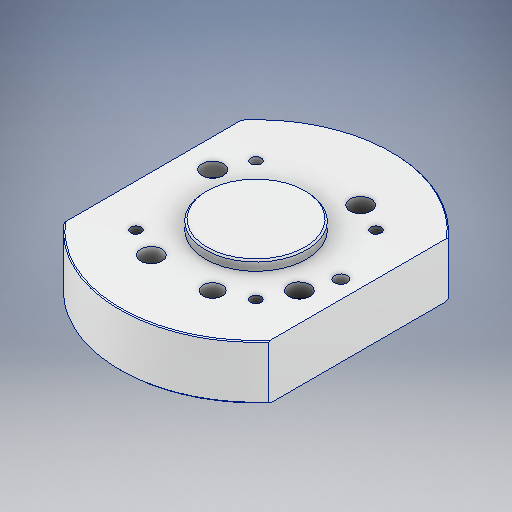
# Autodesk Inventor part: SCHUNK-0302201 A-SWK-020-ISO-A50
Saved by Autodesk Inventor 2025.3 (Build 293356000, 356)
## iProperties
Category: PARTsolutions
Company: SCHUNK
Created: 2026-08-11
Part Number: SCHUNK-0302201 A-SWK-020-ISO-A50
Material: Aluminium 6061
Catalog Web Link: www.3dfindit.com
Description: Adapter plate-Adapter plate
Vendor: SCHUNK
Document SubType Name: Modeling
Designer: psAdmin
Manufacturer: SCHUNK
Mass: 174.754 g
Surface Area: 171.893 cm^2
Volume: 64.7236 cm^3
Density: 2.7 g/cm^3
Appearance: Aluminium - flach
PSOL_IDENT_0: {$CADENAS_DATA/23d-libs/schunk/greifsysteme/roboterzubehoer/wechseln/optionen_fuer_sws/adapterplatte
PSOL_IDENT_1: n/adapterplatten.prj},212 {VTYP=3D},{NB=SCHUNK-0302201 A-SWK-020-ISO-A50},{LINA=SCHUNK-0302201 A-SWK
PSOL_IDENT_2: -020-ISO-A50},{NN=Adapter plate},{DATE=18.09.2025 11:03:46},{GEOMDATE=15.03.2023 10:20:12},{VERSION=
PSOL_IDENT_3: },{LINEID=610},{WBVAR=},{WBNUMERIC=}  {NB=SCHUNK-0302201 A-SWK-020-ISO-A50},{LINA=SCHUNK-0302201 A-S
PSOL_IDENT_4: WK-020-ISO-A50},{KT=8},{IDNR=0302201},{TYP=A-SWK-020-ISO-A50},{PASS=SWK-020/-021},{ONLINE=Zur Produk
PSOL_IDENT_5: tseite},{INFOXX=https://schunk.com/us/en/p/000000000000302201},{VERS=8.000},{D1=85.000},{D2=31.500},
PSOL_IDENT_6: {D3=6.000},{D4=60.000},{T=17.000},{T1=5.700},{T2=12.500},{T3=17.000},{H1=17.000},{H2=3.000},{L1=32.0
PSOL_IDENT_7: 00},{L2=0.000},{L3=26.500},{L4=23.097},{B4=9.567},{L5=18.738},{L6=18.738},{L7=23.097},{L8=9.567},{D5=
PSOL_IDENT_8: 11.000},{D6=6.600},{D7=6.000},{M1=4.000},{M1T=11.300},{K1T=11.300},{W1=0.000},{AZ=0.000},{PX=0.000},
PSOL_IDENT_9: {PY=0.000},{PX1=0.000},{PY1=0.000},{PX2=0.000},{PY2=0.000},{TYP1=1.000},{W2=0.000},{D10=0},{L9=0.000
PSOL_IDENT_10: },{D=33.000},{TI=5.200},{D8=6.600},{D9=31.500},{R1=6.600},{L10=0.000},{L11=0.000},{L12=0.000},{D20=4
PSOL_IDENT_11: .000},{D20L1=26.350},{D20L2=28.750},{D20L3=52.700},{D20L4=57.500},{D20T=6.000},{EPIMID=18062},{PARTS
PSOL_IDENT_12: ERVER=1.000}
NB: SCHUNK-0302201 A-SWK-020-ISO-A50
NN: Adapter plate
NT: Adapter plate
NBSYN: SCHUNK-$IDNR. $TYP.
LINA: SCHUNK-0302201 A-SWK-020-ISO-A50
CATALOG: SCHUNK
IDNR: 0302201
TYP: A-SWK-020-ISO-A50
PASS: SWK-020/-021
ONLINE: To the product page
SUPPLIER: SCHUNK
ARTICLENO: SCHUNK-0302201 A-SWK-020-ISO-A50
BOMINFO: SCHUNK-0302201 A-SWK-020-ISO-A50
CREATOR: CADENAS GmbH
Title: SCHUNK-0302201 A-SWK-020-ISO-A50
Author: Cadenas PARTsolutions
Comments: Adapter plate
Autodesk Inventor part; units mm, degrees
sketch "Sketch_1" plane through (0, 0, 0) normal (1, 0, 0) x (0, 1, 0)
  line L0 (3, 0) -> (-17, 0)
  line L1 (-17, 0) -> (-17, 42)
  line L2 (-17, 42) -> (-16.5, 42.5)
  line L3 (-16.5, 42.5) -> (-0.3, 42.5)
  line L4 (-0.3, 42.5) -> (0, 42.2)
  line L5 (0, 42.2) -> (0, 15.75)
  line L6 (0, 15.75) -> (2.5, 15.75)
  line L7 (2.5, 15.75) -> (3, 15.25)
  line L8 (3, 15.25) -> (3, 0)
  line L9 (3, 0) -> (-17, 0)
  constraints: 20 end point
revolve "Revolution1" add sketch "Sketch_1" angle 360 about axis through (0, 3, 0) along (0, 1, 0)
sketch "Sketch_2" plane through (0, 0, 0) normal (0, 1, 0) x (-1, 0, 0)
  line L0 (-32, -29.4661) -> (-32, 29.4661)
  arc A0 (-32, 29.4661) -> (-32, -29.4661) centre (0, 0) ccw
  constraints: 2 end point, 2 point on circle, 1 centre point
extrude "Extrusion1" cut sketch "Sketch_2" against normal blind 17
sketch "Sketch_3" plane through (0, 0, 0) normal (0, 1, 0) x (-1, 0, 0)
  arc A0 (32, -29.4661) -> (32, 29.4661) centre (0, 0) ccw
  line L0 (32, 29.4661) -> (32, -29.4661)
  constraints: 2 end point, 2 point on circle, 1 centre point
extrude "Extrusion2" cut sketch "Sketch_3" against normal blind 17
sketch "Sketch4" plane through (32, 0, 27.5107) normal (0, 1, 0) x (1, 0, 0)
  point P0 (-5.5, 27.5107)
hole "Hole1" at (26.5, 0, 0) direction (0, -1, 0) diameter 4 depth 17 tip angle 118
sketch "Sketch5" plane through (32, -17, -27.2029) normal (0, -1, 0) x (1, 0, 0)
  point P0 (-32, 27.2029)
hole "Hole2" at (0, -17, 0) direction (0, 1, 0) diameter 60 depth 5.7 countersink diameter 61 countersink angle 90
sketch "Sketch6" plane through (32, 0, 27.5107) normal (0, 1, 0) x (1, 0, 0)
  point P0 (-22.433, 4.4137)
hole "Hole3" at (9.567, 0, 23.097) direction (0, -1, 0) diameter 6 depth 17 tip angle 118
sketch "Sketch_7" plane through (0, 0, 23.097) normal (0, 0, 1) x (1, 0, 0)
  line L0 (-9.567, 0) -> (-9.567, -17)
  line L1 (-9.567, -17) -> (-15.067, -17)
  line L2 (-15.067, -17) -> (-15.067, -4.5)
  line L3 (-15.067, -4.5) -> (-12.867, -4.5)
  line L4 (-12.867, -4.5) -> (-12.867, 0)
  line L5 (-12.867, 0) -> (-9.567, 0)
  line L6 (-9.567, 0) -> (-9.567, -17)
  constraints: 14 end point
revolve "Revolution2" cut sketch "Sketch_7" angle 360 about axis through (-9.567, 0, 23.097) along (0, 1, 0)
pattern_linear "Rectangular Pattern1" count 2 spacing 35.3553 along (0.9239, 0, -0.3827) count 2 spacing 35.3553 along (-0.3827, 0, -0.9239) of "Revolution2"
sketch "Sketch8" plane through (-9.567, -11.3, 23.097) normal (0, -1, 0) x (0.9239, 0, 0.3827)
  point P0 (-24.4823, -35.141)
hole "Hole4" at (-18.738, -11.3, -18.738) direction (0, 1, 0) diameter 3.242 depth 11.5277 tip angle 118 thread size "M4x0.7" class "6H" standard "ISO Metric profile"
pattern_linear "Rectangular Pattern2" count 2 spacing 37.476 along (1, 0, 0) count 2 spacing 37.476 along (0, 0, 1) of "Hole4"
sketch "Sketch9" plane through (32, -17, -27.2029) normal (0, -1, 0) x (1, 0, 0)
  point P0 (-60.75, 0.8529)
hole "Hole5" at (-28.75, -17, -26.35) direction (0, 1, 0) diameter 4 depth 6
pattern_linear "Rectangular Pattern3" count 2 spacing 77.9971 along (0.7372, 0, 0.6757) of "Hole5"
ref_plane "apl_XY" through (0, -11.3, 0) normal (0, 1, 0) x (1, 0, 0)
ref_plane "apl_YZ" through (0, -11.3, 0) normal (1, 0, 0) x (0, 0, -1)
ref_plane "apl_ZX" through (0, -11.3, 0) normal (0, 0, -1) x (0, 1, 0)
body "Solid1"
